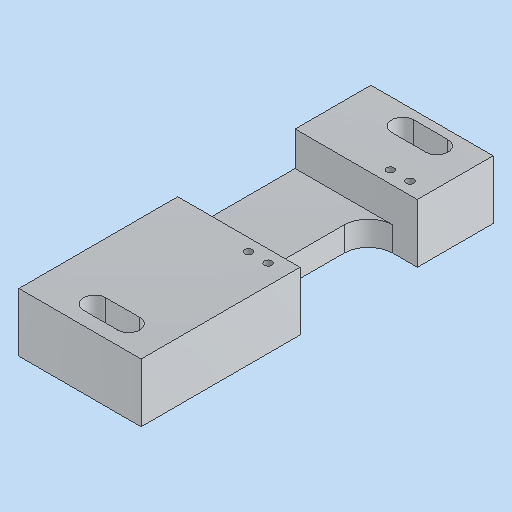
# Autodesk Inventor part: MM0948AN130_G13_104
Saved by Autodesk Inventor 2023.3 (Build 273359000, 359)
## iProperties
Created: 2024-11-12
Part Number: MM0948AN130_G13_104
Material: 3.3547 AlMg4,5Mn0,7 - AW 5083
Description: =<RBPARTNOTITLE2>
Document SubType Name: Modeling
Designer: RIC7AN
Mass: 15.0234 g
Surface Area: 62.6854 cm^2
Volume: 15.0234 cm^3
Density: 1 g/cm^3
Appearance: Aluminium AnP
RBPARTMADEOF: 12 x 72 x 25 (FM)
RBDRAWINGMISSINGSPEC: --
AnP_Kategorie: 1
RBPARTNOTITLE2: Anfertigungsteil
RBSURFACE: anodised colourless
RBPARTNOTITLE1: manufactured part
RBSURFACE2: eloxiert farblos
AnP_Material: =<Material>
RBMATERIAL: =<Material>
RBMATNO: =<Part Number>
RBPARTNO: SIEHE MNR
MaxAbmaße: 12 x 72 x 25 (FM)
Author: RIC7AN
Keywords: =<RBPARTMADEOF>
Comments: =<RBSURFACE2>
Revision Number: 01
Autodesk Inventor part; units mm, degrees
ref_plane "YZ Plane" through (0, 0, 0) normal (1, 0, 0) x (0, 1, 0)
ref_plane "XZ Plane" through (0, 0, 0) normal (0, 1, 0) x (-1, 0, 0)
ref_plane "XY Plane" through (0, 0, 0) normal (0, 0, 1) x (1, 0, 0)
sketch "Skizze1" plane through (0, 0, 0) normal (0, 0, 1) x (1, 0, 0)
  line L0 (0, 15) -> (-67, 15)
  line L1 (-67, 15) -> (-67, 0)
  line L2 (-67, 0) -> (0, 0)
  line L3 (0, 0) -> (0, 15)
  line L4 (0, 86.4) -> (0, -14.4) projected
  line L5 (-80.4, 0) -> (13.4, 0) projected
  line L6 (0, 15) -> (-25, 15)
  line L7 (-25, 15) -> (-25, 72)
  line L8 (-25, 72) -> (0, 72)
  line L9 (0, 72) -> (0, 15)
  line L10 (0, 56.5) -> (-10, 56.5)
  line L11 (-10, 56.5) -> (-10, 32.5)
  line L12 (-10, 32.5) -> (0, 32.5)
  line L13 (0, 32.5) -> (0, 56.5)
  line L14 (-10, 44.5) -> (0, 44.5) construction
  line L15 (-25, 15) -> (-25, 0)
  point P0 (0, 0)
  point P1 (0, 56.5)
  point P2 (0, 72)
  point P3 (0, 32.5)
  dimension "d0" = 67
  dimension "d1" = 15
  dimension "d2" = 72
  dimension "d3" = 25
  dimension "d4" = 24
  dimension "d5" = 10
  dimension "d33" = 32.5
  constraints: 28 end point, 6 parallel, 4 collinear, 3 horizontal, 3 perpendicular, 2 midpoint, 2 point on line, 1 vertical
  measures "d0" distance of L0.start L0.end
  measures "d1" distance of L2.end L0.start
  measures "d2" distance between parallel lines of L2 L8
  measures "d3" distance of L7.end L8.end
  measures "d4" distance of L10.end L11.end
  measures "d5" distance of L10.start L10.end
  measures "d33" distance between parallel lines of L2 L12
extrude "Extrusion1" add sketch "Skizze1" along normal blind 12 contours L3 L2 L15 L0 | L0 L7 L8 L4 L10 L11 L12
sketch "Skizze2" plane through (0, 0, 12) normal (0, 0, 1) x (1, 0, 0)
  line L0 (-10, 32.5) -> (-10, 56.5) projected
  line L1 (-25, 72) -> (-25, 0) projected
  line L2 (-10, 56.5) -> (-25, 56.5)
  line L3 (-25, 56.5) -> (-25, 32.5)
  line L4 (-25, 32.5) -> (-10, 32.5)
  line L5 (-10, 32.5) -> (-10, 56.5)
  point P0 (0, 0)
  point P1 (-25, 15)
  point P2 (-25, 32.5)
  point P3 (-25, 56.5)
  constraints: 8 end point, 2 parallel, 1 collinear, 1 horizontal, 1 perpendicular, 1 point on line
extrude "Extrusion2" cut sketch "Skizze2" against normal blind 7
sketch "Skizze3" plane through (0, 0, 12) normal (0, 0, 1) x (1, 0, 0)
  line L0 (-61.5, 5) -> (-56.5, 5) construction
  line L1 (-61.5, 7.25) -> (-56.5, 7.25)
  line L2 (-56.5, 2.75) -> (-61.5, 2.75)
  arc A0 (-61.5, 7.25) -> (-61.5, 2.75) centre (-61.5, 5) ccw
  arc A1 (-56.5, 2.75) -> (-56.5, 7.25) centre (-56.5, 5) ccw
  line L3 (-14.5, 5) -> (-7.5, 5) construction
  line L4 (-14.5, 7.25) -> (-7.5, 7.25)
  line L5 (-7.5, 2.75) -> (-14.5, 2.75)
  arc A2 (-14.5, 7.25) -> (-14.5, 2.75) centre (-14.5, 5) ccw
  arc A3 (-7.5, 2.75) -> (-7.5, 7.25) centre (-7.5, 5) ccw
  line L6 (-25, 0) -> (0, 0) projected
  line L7 (0, 0) -> (0, 32.5) projected
  line L8 (-14.5, 68) -> (-7.5, 68) construction
  line L9 (-14.5, 70.25) -> (-7.5, 70.25)
  line L10 (-7.5, 65.75) -> (-14.5, 65.75)
  arc A4 (-14.5, 70.25) -> (-14.5, 65.75) centre (-14.5, 68) ccw
  arc A5 (-7.5, 65.75) -> (-7.5, 70.25) centre (-7.5, 68) ccw
  point P0 (-59, 5)
  point P1 (-11, 5)
  point P2 (-11, 68)
  dimension "d11" = 4.5
  dimension "d12" = 5
  dimension "d13" = 48
  dimension "d14" = 5
  dimension "d15" = 7
  dimension "d16" = 11
  dimension "d30" = 63
  dimension "d31" = 4.5
  dimension "d32" = 7
  constraints: 24 end point, 12 point on circle, 12 tangent, 6 centre point, 3 midpoint, 3 parallel, 2 horizontal, 2 point on line, 1 collinear, 1 vertical alignment
  measures "d11" distance between parallel lines of L2 L1
  measures "d12" distance between parallel lines of L6 L0
  measures "d13" distance of point (-11, 5) point (-59, 5)
  measures "d14" distance of L1.start L1.end
  measures "d15" distance of L4.start L4.end
  measures "d16" distance from line of L7 point (-11, 5)
  measures "d30" distance between parallel lines of L3 L8
  measures "d31" distance between parallel lines of L10 L9
  measures "d32" distance of L8.start L8.end
extrude "Extrusion3" cut sketch "Skizze3" against normal through all contours L4 A3 L5 A2 | L9 A5 L10 A4
sketch "Skizze4" plane through (0, 0, 12) normal (0, 0, 1) x (1, 0, 0)
  line L0 (-10, 56.5) -> (0, 56.5) projected
  line L1 (0, 32.5) -> (-10, 32.5) projected
  line L2 (0, 56.5) -> (0, 72) projected
  point P0 (0, 0)
  point P1 (-8, 59)
  point P2 (-4, 59)
  point P3 (-8, 30)
  point P4 (-4, 30)
  point P5 (-25, 57.5)
  point P6 (-25, 32.5)
  dimension "d19" = 4
  dimension "d20" = 2.5
  dimension "d21" = 2.5
  dimension "d22" = 4
  constraints: 2 horizontal alignment, 2 vertical alignment, 1 other
  measures "d19" distance of point (-4, 59) point (-8, 59)
  measures "d21" distance from line of L1 point (-4, 30)
  measures "d22" distance from line of L2 point (-4, 59)
hole "Bohrung1" at (-8, 59, 12) at (-4, 59, 12) at (-8, 30, 12) at (-4, 30, 12) direction (0, 0, -1) diameter 1.567 end through all thread size "M2x0.4" designation "M2" class "6H" standard "ISO Metric profile"
fillet "Rundung1" [suppressed]
fillet "Rundung2" radius 5 2 edges at (-10, 56.5, 2.5) (-10, 32.5, 2.5)
equation "\"d15\" = d32"
equation "\"d21\" = d20"
